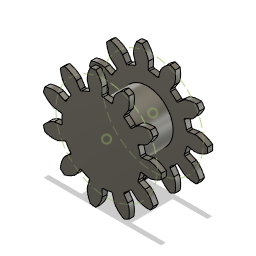
Farm+Robot v19 (Autodesk Fusion 360 archive; units mm, degrees)
design "Gear"
description: Spur Gear; Module: 9.0; Num Teeth: 11; Pressure Angle: 20.0; Backlash: 0.25 mm
Autodesk Fusion 360 part; units mm, degrees
sketch "Sketch1" plane through (0, 0, 0) normal (0, 0, 1) x (1, 0, 0) in component "Spur Gear (11 teeth)"
  circle A0 centre (0, 0) radius 38.6492
extrude "Extrude1" add sketch "Sketch1" along normal blind 5 makes body 1 in component "Spur Gear (11 teeth)"
sketch "Sketch2" plane through (0, 0, 0) normal (0, 0, 1) x (1, 0, 0) in component "Spur Gear (11 teeth)"
  spline S0 degree 5 poles (45.9467, -7.2472) (45.9826, -7.2528) (46.0543, -7.2629) (46.1622, -7.2744) (46.3067, -7.2829) (46.4879, -7.2842) (46.6698, -7.2788) (46.8519, -7.2695) (47.0343, -7.2581) (47.2167, -7.2451) (47.3992, -7.2304) (47.5817, -7.2135) (47.7644, -7.1936) (47.9472, -7.1704) (48.13, -7.1439) (48.313, -7.1144) (48.4959, -7.0824) (48.6788, -7.0482) (48.8616, -7.0121) (49.0444, -6.9742) (49.2272, -6.9345) (49.4098, -6.8928) (49.5924, -6.8491) (49.7749, -6.8033) (49.9573, -6.7554) (50.1396, -6.7056) (50.3218, -6.6539) (50.5038, -6.6004) (50.6857, -6.5453) (50.8674, -6.4884) (51.049, -6.4299) (51.2304, -6.3697) (51.4116, -6.3078) (51.5927, -6.2442) (51.7735, -6.1791) (51.9542, -6.1122) (52.1346, -6.0438) (52.3148, -5.9739) (52.4948, -5.9024) (52.6746, -5.8294) (52.8542, -5.7549) (53.0335, -5.6789) (53.2125, -5.6014) (53.3913, -5.5225) (53.5699, -5.4421) (53.7482, -5.3603) (53.9262, -5.277) (54.1039, -5.1924) (54.2813, -5.1063) (54.4585, -5.0189) (54.6353, -4.9301) (54.8118, -4.8399) (54.9881, -4.7484) (55.164, -4.6556) (55.3396, -4.5614) (55.5149, -4.4659) (55.6898, -4.3692) (55.8644, -4.2711) (56.0387, -4.1717) (56.2126, -4.0711) (56.3862, -3.9692) (56.5594, -3.866) (56.7323, -3.7616) (56.9048, -3.6559) (57.0769, -3.549) (57.2487, -3.4409) (57.4201, -3.3316) (57.591, -3.221) (57.7616, -3.1093) (57.9318, -2.9964) (58.1016, -2.8823) (58.2371, -2.7901) (58.3386, -2.7204) (58.4062, -2.6737) (58.4399, -2.6502) knots 0 0 0 0 0 0 0.01428571 0.02857143 0.04285714 0.05714286 0.07142857 0.08571429 0.1 0.11428571 0.12857143 0.14285714 0.15714286 0.17142857 0.18571429 0.2 0.21428571 0.22857143 0.24285714 0.25714286 0.27142857 0.28571429 0.3 0.31428571 0.32857143 0.34285714 0.35714286 0.37142857 0.38571429 0.4 0.41428571 0.42857143 0.44285714 0.45714286 0.47142857 0.48571429 0.5 0.51428571 0.52857143 0.54285714 0.55714286 0.57142857 0.58571429 0.6 0.61428571 0.62857143 0.64285714 0.65714286 0.67142857 0.68571429 0.7 0.71428571 0.72857143 0.74285714 0.75714286 0.77142857 0.78571429 0.8 0.81428571 0.82857143 0.84285714 0.85714286 0.87142857 0.88571429 0.9 0.91428571 0.92857143 0.94285714 0.95714286 0.97142857 0.98571429 1 1 1 1 1 1
  spline S1 degree 5 poles (45.9467, 7.2472) (45.9826, 7.2528) (46.0543, 7.2629) (46.1622, 7.2744) (46.3067, 7.2829) (46.4879, 7.2842) (46.6698, 7.2788) (46.8519, 7.2695) (47.0343, 7.2581) (47.2167, 7.2451) (47.3992, 7.2304) (47.5817, 7.2135) (47.7644, 7.1936) (47.9472, 7.1704) (48.13, 7.1439) (48.313, 7.1144) (48.4959, 7.0824) (48.6788, 7.0482) (48.8616, 7.0121) (49.0444, 6.9742) (49.2272, 6.9345) (49.4098, 6.8928) (49.5924, 6.8491) (49.7749, 6.8033) (49.9573, 6.7554) (50.1396, 6.7056) (50.3218, 6.6539) (50.5038, 6.6004) (50.6857, 6.5453) (50.8674, 6.4884) (51.049, 6.4299) (51.2304, 6.3697) (51.4116, 6.3078) (51.5927, 6.2442) (51.7735, 6.1791) (51.9542, 6.1122) (52.1346, 6.0438) (52.3148, 5.9739) (52.4948, 5.9024) (52.6746, 5.8294) (52.8542, 5.7549) (53.0335, 5.6789) (53.2125, 5.6014) (53.3913, 5.5225) (53.5699, 5.4421) (53.7482, 5.3603) (53.9262, 5.277) (54.1039, 5.1924) (54.2813, 5.1063) (54.4585, 5.0189) (54.6353, 4.9301) (54.8118, 4.8399) (54.9881, 4.7484) (55.164, 4.6556) (55.3396, 4.5614) (55.5149, 4.4659) (55.6898, 4.3692) (55.8644, 4.2711) (56.0387, 4.1717) (56.2126, 4.0711) (56.3862, 3.9692) (56.5594, 3.866) (56.7323, 3.7616) (56.9048, 3.6559) (57.0769, 3.549) (57.2487, 3.4409) (57.4201, 3.3316) (57.591, 3.221) (57.7616, 3.1093) (57.9318, 2.9964) (58.1016, 2.8823) (58.2371, 2.7901) (58.3386, 2.7204) (58.4062, 2.6737) (58.4399, 2.6502) knots 0 0 0 0 0 0 0.01428571 0.02857143 0.04285714 0.05714286 0.07142857 0.08571429 0.1 0.11428571 0.12857143 0.14285714 0.15714286 0.17142857 0.18571429 0.2 0.21428571 0.22857143 0.24285714 0.25714286 0.27142857 0.28571429 0.3 0.31428571 0.32857143 0.34285714 0.35714286 0.37142857 0.38571429 0.4 0.41428571 0.42857143 0.44285714 0.45714286 0.47142857 0.48571429 0.5 0.51428571 0.52857143 0.54285714 0.55714286 0.57142857 0.58571429 0.6 0.61428571 0.62857143 0.64285714 0.65714286 0.67142857 0.68571429 0.7 0.71428571 0.72857143 0.74285714 0.75714286 0.77142857 0.78571429 0.8 0.81428571 0.82857143 0.84285714 0.85714286 0.87142857 0.88571429 0.9 0.91428571 0.92857143 0.94285714 0.95714286 0.97142857 0.98571429 1 1 1 1 1 1
  arc A0 (58.4399, -2.6502) -> (58.4399, 2.6502) centre (0, 0) ccw
  line L0 (38.1673, -6.0217) -> (45.9467, -7.2472)
  line L1 (38.1673, 6.0217) -> (45.9467, 7.2472)
  line L2 (38.1673, -6.0217) -> (38.1673, 6.0217)
  point P0 (46.8095, -7.2713)
  point P1 (47.6862, -7.2017)
  point P2 (48.5715, -7.068)
  point P3 (49.463, -6.8798)
  point P4 (50.359, -6.6426)
  point P5 (51.2583, -6.3598)
  point P6 (52.1596, -6.0338)
  point P7 (53.0618, -5.6664)
  point P8 (53.9639, -5.2588)
  point P9 (54.865, -4.8121)
  point P10 (55.7641, -4.3273)
  point P11 (56.6602, -3.8049)
  point P12 (57.5525, -3.2457)
  point P13 (46.8095, 7.2713)
  point P14 (47.6862, 7.2017)
  point P15 (48.5715, 7.068)
  point P16 (49.463, 6.8798)
  point P17 (50.359, 6.6426)
  point P18 (51.2583, 6.3598)
  point P19 (52.1596, 6.0338)
  point P20 (53.0618, 5.6664)
  point P21 (53.9639, 5.2588)
  point P22 (54.865, 4.8121)
  point P23 (55.7641, 4.3273)
  point P24 (56.6602, 3.8049)
  point P25 (57.5525, 3.2457)
extrude "Extrude2" add sketch "Sketch2" along normal blind 5 bodies 1 in component "Spur Gear (11 teeth)"
fillet "Fillet1" radius 1.1 2 edges at (38.177, -6.0232, 2.5) (38.177, 6.0232, 2.5) on bodies 1 in component "Spur Gear (11 teeth)"
pattern_circular "C-Pattern1" count 11 over 360 about axis through (0, 0, 0) along (0, 0, 1) of "Extrude2", "Fillet1" in component "Spur Gear (11 teeth)"
sketch "Sketch3" plane through (0, 0, 0) normal (0, 0, 1) x (1, 0, 0) in component "Spur Gear (11 teeth)"
  circle A0 centre (0, 0) radius 49.5 construction
cylinder "CylinderPrimitive1" add diameter 50 height 40 placed x (1, 0, 0) y (0, 1, 0) z (0, 0, 1) at (86.8114, 17.2238, 0) separate body makes body 2
move_body "Move1" bodies 2 to x (1, 0, 0) y (0, 1, 0) z (0, 0, 1) at (3, -2, 0)
copy_body "Body->Comp1" bodies 2 removing the originals makes body 3 in component "Component"
component "Spur Gear (11 teeth)" placed x (1, 0, 0) y (0, 1, 0) z (0, 0, 1) at (0.2, -0.3, -5)
component "Spur Gear (11 teeth)" placed x (1, 0, 0) y (0, 1, 0) z (0, 0, 1) at (0, 0, 40)
component "Component" placed x (1, 0, 0) y (0, 1, 0) z (0, 0, 1) at (-89.8, -15.3, 0)
